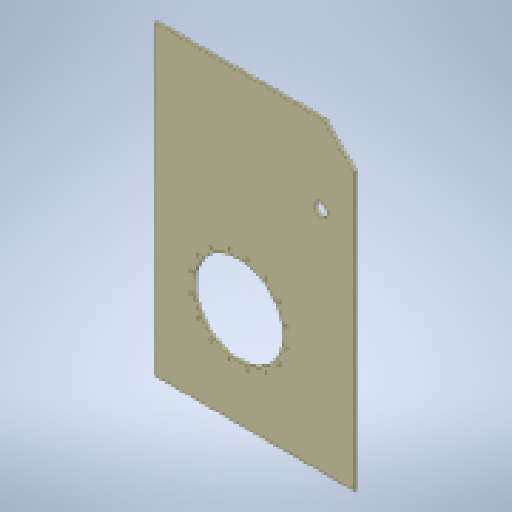
# Autodesk Inventor part: DMF-3012 Front Wall Dummy
Saved by Autodesk Inventor 2026.2 (Build 302298000, 298)
## iProperties
Created: 2023-08-31
Part Number: DMF-3012 Front Wall Dummy
Material: Polypropylene
Document SubType Name: Sheet Metal
Designer: admin
Stock Number: DMF-3012
Density: 0.899 g/cm^3
Sheet Metal Rule: Default
Sheet Metal Width: 920,000 mm
Sheet Metal Length: 1410,000 mm
Sheet Metal Area: 1297200,000 mm^2
Appearance: Smooth - Ash
Flat Pattern Width: 92 cm
Flat Pattern Length: 141 cm
Flat Pattern Area: 12972 cm^2
Author: admin
Autodesk Inventor part; units mm, degrees
ref_plane "YZ Plane" through (0, 0, 0) normal (1, 0, 0) x (0, 1, 0)
ref_plane "XZ Plane" through (0, 0, 0) normal (0, 1, 0) x (-1, 0, 0)
ref_plane "XY Plane" through (0, 0, 0) normal (0, 0, 1) x (1, 0, 0)
sketch "Sketch7" plane through (0, 0, 0) normal (0, 0, 1) x (1, 0, 0)
  line L0 (515, 1910) -> (-325, 1910)
  line L1 (-325, 1910) -> (-1085, 1150)
  line L2 (-1085, 0) -> (-1085, 1150)
  line L3 (1085, 0) -> (1085, 1340)
  line L4 (515, 1910) -> (1085, 1340)
  line L5 (1085, 0) -> (-1085, 0)
  circle A0 centre (120, 955) radius 700 construction
  line L6 (499.31, -455.1177) -> (499.31, 1910) construction
  circle A1 centre (499.31, 1543.323) radius 30
  line L7 (1085, 955) -> (325, 955) construction
  circle A2 centre (120, 955) radius 205
  line L8 (120, 0) -> (120, 750) construction
  circle A3 centre (120, 955) radius 225 construction
  circle A4 centre (163.8953, 1175.6767) radius 6
  line L9 (120, 955) -> (120, 1180) construction
  line L10 (163.8953, 1175.6767) -> (120, 955) construction
  circle A5 centre (76.1047, 1175.6767) radius 6
  circle A6 centre (-5.0033, 1142.0807) radius 6
  circle A7 centre (-67.0807, 1080.0033) radius 6
  circle A8 centre (-100.6767, 998.8953) radius 6
  circle A9 centre (-100.6767, 911.1047) radius 6
  circle A10 centre (-67.0807, 829.9967) radius 6
  circle A11 centre (-5.0033, 767.9193) radius 6
  circle A12 centre (76.1047, 734.3233) radius 6
  circle A13 centre (163.8953, 734.3233) radius 6
  circle A14 centre (245.0033, 767.9193) radius 6
  circle A15 centre (307.0807, 829.9967) radius 6
  circle A16 centre (340.6767, 911.1047) radius 6
  circle A17 centre (340.6767, 998.8953) radius 6
  circle A18 centre (307.0807, 1080.0033) radius 6
  circle A19 centre (245.0033, 1142.0807) radius 6
  circle A20 centre (120, 955) radius 670 construction
  line L11 (655, 1770) -> (655, 500)
  line L12 (655, 500) -> (-265, 500)
  line L13 (-265, 500) -> (-265, 1910)
  point P0 (0, 0)
  point P1 (0, 0)
  dimension "d113" = 1400
  dimension "d101" = 840
  dimension "d102" = 1150
  dimension "d104" = 1910
  dimension "d109" = 2170
  dimension "d111" = 806.1017
  dimension "d112" = 1074.8023
  dimension "d114" = 1584.31
  dimension "d115" = 60
  dimension "d116" = 760
  dimension "d117" = 410
  dimension "d118" = 750
  dimension "d119" = 450
  dimension "d120" = 12
  dimension "d121" = 11.25
  dimension "d122" = 360
  dimension "d123" = 465
  dimension "d125" = 820
  dimension "d126" = 430
  dimension "d127" = 500
  dimension "d128" = 135
  dimension "d129" = 135
  measures "d101" distance of L4.start L0.end
  measures "d102" distance of L2.start L1.end
  measures "d104" vertical distance of L2.start L0.end
  measures "d109" distance of L3.start L2.start
  measures "d111" distance of L4.start L4.end
  measures "d112" distance of L0.end L1.end
  measures "d114" distance between parallel lines of L2 L6
  measures "d115" diameter of A1
  measures "d116" distance of L7.start L7.end
  measures "d117" diameter of A2
  measures "d118" distance of L8.start L8.end
  measures "d119" diameter of A3
  measures "d120" diameter of A4
  measures "d121" angle of L9 L10
  measures "d123" radial gap between concentric circles of A2 A20
  measures "d125" distance between parallel lines of L2 L13
  measures "d126" distance between parallel lines of L3 L11
  measures "d127" distance between parallel lines of L5 L12
  measures "d128" angle of L0 L1
  measures "d129" angle of L4 L0
extrude "Plate1" add sketch "Sketch7" along normal blind 10 contours L4 L11 L12 L13 L0
body "Solid3"
